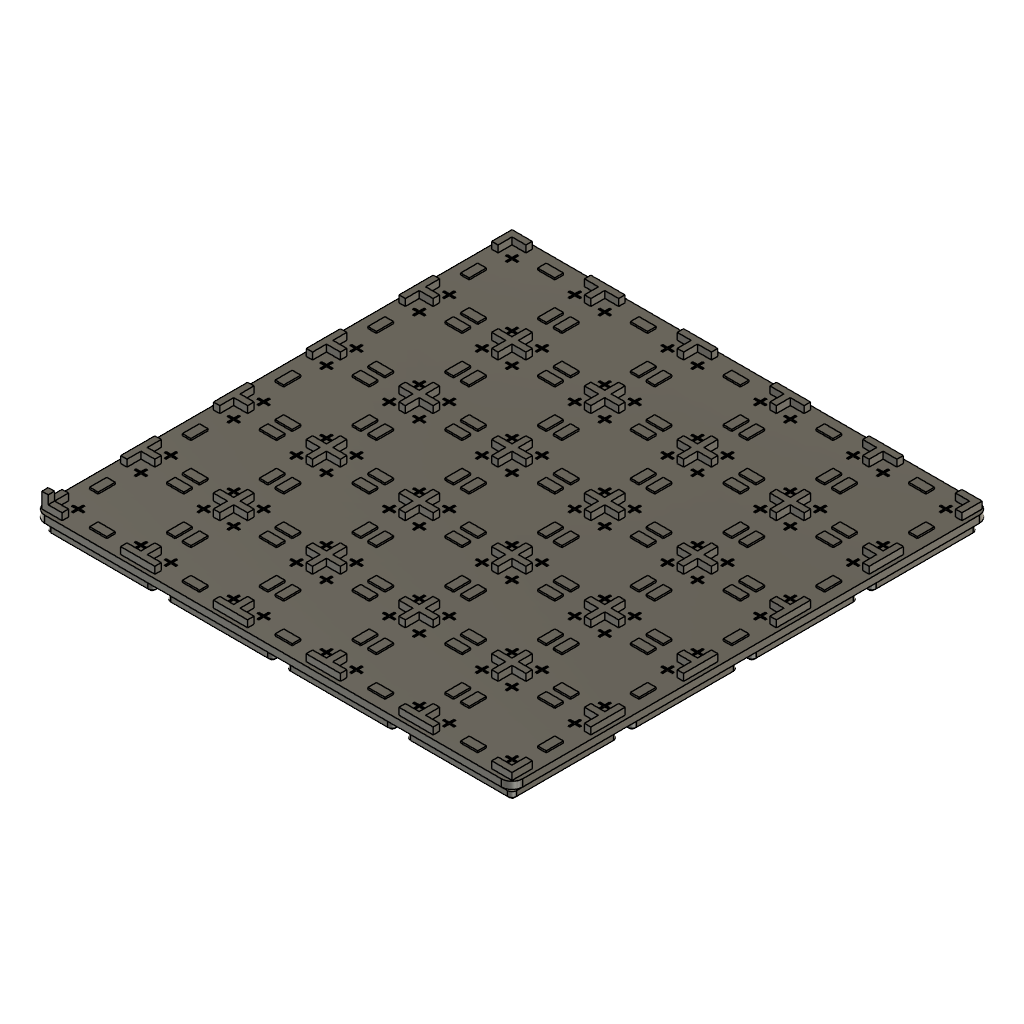
da-lab3-tilgaplaat-v3 (Autodesk Fusion 360 design; units mm, degrees)
part number: 2026-11-14-15-51-29-594
part number: 2026-11-14-15-51-29-835
Autodesk Fusion 360 part; units mm, degrees
(part 1 of 3)
ref_plane "WorkPlane1" through (0, 0, 4.75) normal (0, 0, 1) x (1, 0, 0) in component "drop_plate"
sketch "plate" plane through (0, 0, 4.75) normal (0, 0, 1) x (1, 0, 0) in component "drop_plate"
  line L0 (-80, -83.75) -> (80, -83.75)
  line L1 (83.75, -80) -> (83.75, 80)
  line L2 (80, 83.75) -> (-80, 83.75)
  line L3 (-83.75, 80) -> (-83.75, -80)
  arc A0 (80, -83.75) -> (83.75, -80) centre (80, -80) ccw
  arc A1 (83.75, 80) -> (80, 83.75) centre (80, 80) ccw
  arc A2 (-80, 83.75) -> (-83.75, 80) centre (-80, 80) ccw
  arc A3 (-83.75, -80) -> (-80, -83.75) centre (-80, -80) ccw
  constraint tangent L0 A0
  constraint tangent L1 A0
  constraint tangent L1 A1
  constraint tangent L2 A1
  constraint tangent L2 A2
  constraint tangent L3 A2
  constraint tangent L3 A3
  constraint tangent L0 A3
extrude "plate (1)" add sketch "plate" along normal blind 2.5 in component "drop_plate"
ref_plane "WorkPlane2" through (0, 0, 4.75) normal (0, 0, 1) x (1, 0, 0) in component "drop_plate"
sketch "gf_std_foot1" plane through (0, 0, 4.75) normal (0, 0, 1) x (1, 0, 0) in component "drop_plate"
  line L0 (-46, -42.25) -> (-80, -42.25)
  line L1 (-83.75, -46) -> (-83.75, -80)
  line L2 (-80, -83.75) -> (-46, -83.75)
  line L3 (-42.25, -80) -> (-42.25, -46)
  arc A0 (-80, -42.25) -> (-83.75, -46) centre (-80, -46) ccw
  arc A1 (-83.75, -80) -> (-80, -83.75) centre (-80, -80) ccw
  arc A2 (-46, -83.75) -> (-42.25, -80) centre (-46, -80) ccw
  arc A3 (-42.25, -46) -> (-46, -42.25) centre (-46, -46) ccw
  line L4 (-46, -0.25) -> (-80, -0.25)
  line L5 (-83.75, -4) -> (-83.75, -38)
  line L6 (-80, -41.75) -> (-46, -41.75)
  line L7 (-42.25, -38) -> (-42.25, -4)
  arc A4 (-80, -0.25) -> (-83.75, -4) centre (-80, -4) ccw
  arc A5 (-83.75, -38) -> (-80, -41.75) centre (-80, -38) ccw
  arc A6 (-46, -41.75) -> (-42.25, -38) centre (-46, -38) ccw
  arc A7 (-42.25, -4) -> (-46, -0.25) centre (-46, -4) ccw
  line L8 (-46, 41.75) -> (-80, 41.75)
  line L9 (-83.75, 38) -> (-83.75, 4)
  line L10 (-80, 0.25) -> (-46, 0.25)
  line L11 (-42.25, 4) -> (-42.25, 38)
  arc A8 (-80, 41.75) -> (-83.75, 38) centre (-80, 38) ccw
  arc A9 (-83.75, 4) -> (-80, 0.25) centre (-80, 4) ccw
  arc A10 (-46, 0.25) -> (-42.25, 4) centre (-46, 4) ccw
  arc A11 (-42.25, 38) -> (-46, 41.75) centre (-46, 38) ccw
  line L12 (-46, 83.75) -> (-80, 83.75)
  line L13 (-83.75, 80) -> (-83.75, 46)
  line L14 (-80, 42.25) -> (-46, 42.25)
  line L15 (-42.25, 46) -> (-42.25, 80)
  arc A12 (-80, 83.75) -> (-83.75, 80) centre (-80, 80) ccw
  arc A13 (-83.75, 46) -> (-80, 42.25) centre (-80, 46) ccw
  arc A14 (-46, 42.25) -> (-42.25, 46) centre (-46, 46) ccw
  arc A15 (-42.25, 80) -> (-46, 83.75) centre (-46, 80) ccw
  line L16 (-4, -42.25) -> (-38, -42.25)
  line L17 (-41.75, -46) -> (-41.75, -80)
  line L18 (-38, -83.75) -> (-4, -83.75)
  line L19 (-0.25, -80) -> (-0.25, -46)
  arc A16 (-38, -42.25) -> (-41.75, -46) centre (-38, -46) ccw
  arc A17 (-41.75, -80) -> (-38, -83.75) centre (-38, -80) ccw
  arc A18 (-4, -83.75) -> (-0.25, -80) centre (-4, -80) ccw
  arc A19 (-0.25, -46) -> (-4, -42.25) centre (-4, -46) ccw
  line L20 (-4, -0.25) -> (-38, -0.25)
  line L21 (-41.75, -4) -> (-41.75, -38)
  line L22 (-38, -41.75) -> (-4, -41.75)
  line L23 (-0.25, -38) -> (-0.25, -4)
  arc A20 (-38, -0.25) -> (-41.75, -4) centre (-38, -4) ccw
  arc A21 (-41.75, -38) -> (-38, -41.75) centre (-38, -38) ccw
  arc A22 (-4, -41.75) -> (-0.25, -38) centre (-4, -38) ccw
  arc A23 (-0.25, -4) -> (-4, -0.25) centre (-4, -4) ccw
  line L24 (-4, 41.75) -> (-38, 41.75)
  line L25 (-41.75, 38) -> (-41.75, 4)
  line L26 (-38, 0.25) -> (-4, 0.25)
  line L27 (-0.25, 4) -> (-0.25, 38)
  arc A24 (-38, 41.75) -> (-41.75, 38) centre (-38, 38) ccw
  arc A25 (-41.75, 4) -> (-38, 0.25) centre (-38, 4) ccw
  arc A26 (-4, 0.25) -> (-0.25, 4) centre (-4, 4) ccw
  arc A27 (-0.25, 38) -> (-4, 41.75) centre (-4, 38) ccw
  line L28 (-4, 83.75) -> (-38, 83.75)
  line L29 (-41.75, 80) -> (-41.75, 46)
  line L30 (-38, 42.25) -> (-4, 42.25)
  line L31 (-0.25, 46) -> (-0.25, 80)
  arc A28 (-38, 83.75) -> (-41.75, 80) centre (-38, 80) ccw
  arc A29 (-41.75, 46) -> (-38, 42.25) centre (-38, 46) ccw
  arc A30 (-4, 42.25) -> (-0.25, 46) centre (-4, 46) ccw
  arc A31 (-0.25, 80) -> (-4, 83.75) centre (-4, 80) ccw
  line L32 (38, -42.25) -> (4, -42.25)
  line L33 (0.25, -46) -> (0.25, -80)
  line L34 (4, -83.75) -> (38, -83.75)
  line L35 (41.75, -80) -> (41.75, -46)
  arc A32 (4, -42.25) -> (0.25, -46) centre (4, -46) ccw
  arc A33 (0.25, -80) -> (4, -83.75) centre (4, -80) ccw
  arc A34 (38, -83.75) -> (41.75, -80) centre (38, -80) ccw
  arc A35 (41.75, -46) -> (38, -42.25) centre (38, -46) ccw
  line L36 (38, -0.25) -> (4, -0.25)
  line L37 (0.25, -4) -> (0.25, -38)
  line L38 (4, -41.75) -> (38, -41.75)
  line L39 (41.75, -38) -> (41.75, -4)
  arc A36 (4, -0.25) -> (0.25, -4) centre (4, -4) ccw
  arc A37 (0.25, -38) -> (4, -41.75) centre (4, -38) ccw
  arc A38 (38, -41.75) -> (41.75, -38) centre (38, -38) ccw
  arc A39 (41.75, -4) -> (38, -0.25) centre (38, -4) ccw
  line L40 (38, 41.75) -> (4, 41.75)
  line L41 (0.25, 38) -> (0.25, 4)
  line L42 (4, 0.25) -> (38, 0.25)
  line L43 (41.75, 4) -> (41.75, 38)
  arc A40 (4, 41.75) -> (0.25, 38) centre (4, 38) ccw
  arc A41 (0.25, 4) -> (4, 0.25) centre (4, 4) ccw
  arc A42 (38, 0.25) -> (41.75, 4) centre (38, 4) ccw
  arc A43 (41.75, 38) -> (38, 41.75) centre (38, 38) ccw
  line L44 (38, 83.75) -> (4, 83.75)
  line L45 (0.25, 80) -> (0.25, 46)
  line L46 (4, 42.25) -> (38, 42.25)
  line L47 (41.75, 46) -> (41.75, 80)
  arc A44 (4, 83.75) -> (0.25, 80) centre (4, 80) ccw
  arc A45 (0.25, 46) -> (4, 42.25) centre (4, 46) ccw
  arc A46 (38, 42.25) -> (41.75, 46) centre (38, 46) ccw
  arc A47 (41.75, 80) -> (38, 83.75) centre (38, 80) ccw
  line L48 (80, -42.25) -> (46, -42.25)
  line L49 (42.25, -46) -> (42.25, -80)
  line L50 (46, -83.75) -> (80, -83.75)
  line L51 (83.75, -80) -> (83.75, -46)
  arc A48 (46, -42.25) -> (42.25, -46) centre (46, -46) ccw
  arc A49 (42.25, -80) -> (46, -83.75) centre (46, -80) ccw
  arc A50 (80, -83.75) -> (83.75, -80) centre (80, -80) ccw
  arc A51 (83.75, -46) -> (80, -42.25) centre (80, -46) ccw
  line L52 (80, -0.25) -> (46, -0.25)
  line L53 (42.25, -4) -> (42.25, -38)
  line L54 (46, -41.75) -> (80, -41.75)
  line L55 (83.75, -38) -> (83.75, -4)
  arc A52 (46, -0.25) -> (42.25, -4) centre (46, -4) ccw
  arc A53 (42.25, -38) -> (46, -41.75) centre (46, -38) ccw
  arc A54 (80, -41.75) -> (83.75, -38) centre (80, -38) ccw
  arc A55 (83.75, -4) -> (80, -0.25) centre (80, -4) ccw
  line L56 (80, 41.75) -> (46, 41.75)
  line L57 (42.25, 38) -> (42.25, 4)
  line L58 (46, 0.25) -> (80, 0.25)
  line L59 (83.75, 4) -> (83.75, 38)
  arc A56 (46, 41.75) -> (42.25, 38) centre (46, 38) ccw
  arc A57 (42.25, 4) -> (46, 0.25) centre (46, 4) ccw
  arc A58 (80, 0.25) -> (83.75, 4) centre (80, 4) ccw
  arc A59 (83.75, 38) -> (80, 41.75) centre (80, 38) ccw
  line L60 (80, 83.75) -> (46, 83.75)
  line L61 (42.25, 80) -> (42.25, 46)
  line L62 (46, 42.25) -> (80, 42.25)
  line L63 (83.75, 46) -> (83.75, 80)
  arc A60 (46, 83.75) -> (42.25, 80) centre (46, 80) ccw
  arc A61 (42.25, 46) -> (46, 42.25) centre (46, 46) ccw
  arc A62 (80, 42.25) -> (83.75, 46) centre (80, 46) ccw
  arc A63 (83.75, 80) -> (80, 83.75) centre (80, 80) ccw
  constraint tangent L0 A0
  constraint tangent L1 A0
  constraint tangent L1 A1
  constraint tangent L2 A1
  constraint tangent L2 A2
  constraint tangent L3 A2
  constraint tangent L3 A3
  constraint tangent L0 A3
  constraint tangent L4 A4
  constraint tangent L5 A4
  constraint tangent L5 A5
  constraint tangent L6 A5
  constraint tangent L6 A6
  constraint tangent L7 A6
  constraint tangent L7 A7
  constraint tangent L4 A7
  constraint tangent L8 A8
  constraint tangent L9 A8
  constraint tangent L9 A9
  constraint tangent L10 A9
  constraint tangent L10 A10
  constraint tangent L11 A10
  constraint tangent L11 A11
  constraint tangent L8 A11
  constraint tangent L12 A12
  constraint tangent L13 A12
  constraint tangent L13 A13
  constraint tangent L14 A13
  constraint tangent L14 A14
  constraint tangent L15 A14
  constraint tangent L15 A15
  constraint tangent L12 A15
  constraint tangent L16 A16
  constraint tangent L17 A16
  constraint tangent L17 A17
  constraint tangent L18 A17
  constraint tangent L18 A18
  constraint tangent L19 A18
  constraint tangent L19 A19
  constraint tangent L16 A19
  constraint tangent L20 A20
  constraint tangent L21 A20
  constraint tangent L21 A21
  constraint tangent L22 A21
  constraint tangent L22 A22
  constraint tangent L23 A22
  constraint tangent L23 A23
  constraint tangent L20 A23
  constraint tangent L24 A24
  constraint tangent L25 A24
  constraint tangent L25 A25
  constraint tangent L26 A25
  constraint tangent L26 A26
  constraint tangent L27 A26
  constraint tangent L27 A27
  constraint tangent L24 A27
  constraint tangent L28 A28
  constraint tangent L29 A28
  constraint tangent L29 A29
  constraint tangent L30 A29
  constraint tangent L30 A30
  constraint tangent L31 A30
  constraint tangent L31 A31
  constraint tangent L28 A31
  constraint tangent L32 A32
  constraint tangent L33 A32
  constraint tangent L33 A33
  constraint tangent L34 A33
  constraint tangent L34 A34
  constraint tangent L35 A34
  constraint tangent L35 A35
  constraint tangent L32 A35
  constraint tangent L36 A36
  constraint tangent L37 A36
  constraint tangent L37 A37
  constraint tangent L38 A37
  constraint tangent L38 A38
  constraint tangent L39 A38
  constraint tangent L39 A39
  constraint tangent L36 A39
  constraint tangent L40 A40
  constraint tangent L41 A40
  constraint tangent L41 A41
  constraint tangent L42 A41
  constraint tangent L42 A42
  constraint tangent L43 A42
  constraint tangent L43 A43
  constraint tangent L40 A43
  constraint tangent L44 A44
  constraint tangent L45 A44
  constraint tangent L45 A45
  constraint tangent L46 A45
  constraint tangent L46 A46
  constraint tangent L47 A46
  constraint tangent L47 A47
  constraint tangent L44 A47
  constraint tangent L48 A48
  constraint tangent L49 A48
  constraint tangent L49 A49
  constraint tangent L50 A49
  constraint tangent L50 A50
  constraint tangent L51 A50
  constraint tangent L51 A51
  constraint tangent L48 A51
  constraint tangent L52 A52
  constraint tangent L53 A52
  constraint tangent L53 A53
  constraint tangent L54 A53
  constraint tangent L54 A54
  constraint tangent L55 A54
  constraint tangent L55 A55
  constraint tangent L52 A55
  constraint tangent L56 A56
  constraint tangent L57 A56
  constraint tangent L57 A57
  constraint tangent L58 A57
  constraint tangent L58 A58
  constraint tangent L59 A58
  constraint tangent L59 A59
  constraint tangent L56 A59
  constraint tangent L60 A60
  constraint tangent L61 A60
  constraint tangent L61 A61
  constraint tangent L62 A61
  constraint tangent L62 A62
  constraint tangent L63 A62
  constraint tangent L63 A63
  constraint tangent L60 A63
extrude "gf_std_foot1 (1)" add sketch "gf_std_foot1" against normal blind 2.15 draft -45 in component "drop_plate"
ref_plane "WorkPlane3" through (0, 0, 2.6) normal (0, 0, 1) x (1, 0, 0) in component "drop_plate"
sketch "gf_std_foot2" plane through (0, 0, 2.6) normal (0, 0, 1) x (1, 0, 0) in component "drop_plate"
  line L0 (-46, -44.4) -> (-80, -44.4)
  line L1 (-81.6, -46) -> (-81.6, -80)
  line L2 (-80, -81.6) -> (-46, -81.6)
  line L3 (-44.4, -80) -> (-44.4, -46)
  arc A0 (-80, -44.4) -> (-81.6, -46) centre (-80, -46) ccw
  arc A1 (-81.6, -80) -> (-80, -81.6) centre (-80, -80) ccw
  arc A2 (-46, -81.6) -> (-44.4, -80) centre (-46, -80) ccw
  arc A3 (-44.4, -46) -> (-46, -44.4) centre (-46, -46) ccw
  line L4 (-46, -2.4) -> (-80, -2.4)
  line L5 (-81.6, -4) -> (-81.6, -38)
  line L6 (-80, -39.6) -> (-46, -39.6)
  line L7 (-44.4, -38) -> (-44.4, -4)
  arc A4 (-80, -2.4) -> (-81.6, -4) centre (-80, -4) ccw
  arc A5 (-81.6, -38) -> (-80, -39.6) centre (-80, -38) ccw
  arc A6 (-46, -39.6) -> (-44.4, -38) centre (-46, -38) ccw
  arc A7 (-44.4, -4) -> (-46, -2.4) centre (-46, -4) ccw
  line L8 (-46, 39.6) -> (-80, 39.6)
  line L9 (-81.6, 38) -> (-81.6, 4)
  line L10 (-80, 2.4) -> (-46, 2.4)
  line L11 (-44.4, 4) -> (-44.4, 38)
  arc A8 (-80, 39.6) -> (-81.6, 38) centre (-80, 38) ccw
  arc A9 (-81.6, 4) -> (-80, 2.4) centre (-80, 4) ccw
  arc A10 (-46, 2.4) -> (-44.4, 4) centre (-46, 4) ccw
  arc A11 (-44.4, 38) -> (-46, 39.6) centre (-46, 38) ccw
  line L12 (-46, 81.6) -> (-80, 81.6)
  line L13 (-81.6, 80) -> (-81.6, 46)
  line L14 (-80, 44.4) -> (-46, 44.4)
  line L15 (-44.4, 46) -> (-44.4, 80)
  arc A12 (-80, 81.6) -> (-81.6, 80) centre (-80, 80) ccw
  arc A13 (-81.6, 46) -> (-80, 44.4) centre (-80, 46) ccw
  arc A14 (-46, 44.4) -> (-44.4, 46) centre (-46, 46) ccw
  arc A15 (-44.4, 80) -> (-46, 81.6) centre (-46, 80) ccw
  line L16 (-4, -44.4) -> (-38, -44.4)
  line L17 (-39.6, -46) -> (-39.6, -80)
  line L18 (-38, -81.6) -> (-4, -81.6)
  line L19 (-2.4, -80) -> (-2.4, -46)
  arc A16 (-38, -44.4) -> (-39.6, -46) centre (-38, -46) ccw
  arc A17 (-39.6, -80) -> (-38, -81.6) centre (-38, -80) ccw
  arc A18 (-4, -81.6) -> (-2.4, -80) centre (-4, -80) ccw
  arc A19 (-2.4, -46) -> (-4, -44.4) centre (-4, -46) ccw
  line L20 (-4, -2.4) -> (-38, -2.4)
  line L21 (-39.6, -4) -> (-39.6, -38)
  line L22 (-38, -39.6) -> (-4, -39.6)
  line L23 (-2.4, -38) -> (-2.4, -4)
  arc A20 (-38, -2.4) -> (-39.6, -4) centre (-38, -4) ccw
  arc A21 (-39.6, -38) -> (-38, -39.6) centre (-38, -38) ccw
  arc A22 (-4, -39.6) -> (-2.4, -38) centre (-4, -38) ccw
  arc A23 (-2.4, -4) -> (-4, -2.4) centre (-4, -4) ccw
  line L24 (-4, 39.6) -> (-38, 39.6)
  line L25 (-39.6, 38) -> (-39.6, 4)
  line L26 (-38, 2.4) -> (-4, 2.4)
  line L27 (-2.4, 4) -> (-2.4, 38)
  arc A24 (-38, 39.6) -> (-39.6, 38) centre (-38, 38) ccw
  arc A25 (-39.6, 4) -> (-38, 2.4) centre (-38, 4) ccw
  arc A26 (-4, 2.4) -> (-2.4, 4) centre (-4, 4) ccw
  arc A27 (-2.4, 38) -> (-4, 39.6) centre (-4, 38) ccw
  line L28 (-4, 81.6) -> (-38, 81.6)
  line L29 (-39.6, 80) -> (-39.6, 46)
  line L30 (-38, 44.4) -> (-4, 44.4)
  line L31 (-2.4, 46) -> (-2.4, 80)
  arc A28 (-38, 81.6) -> (-39.6, 80) centre (-38, 80) ccw
  arc A29 (-39.6, 46) -> (-38, 44.4) centre (-38, 46) ccw
  arc A30 (-4, 44.4) -> (-2.4, 46) centre (-4, 46) ccw
  arc A31 (-2.4, 80) -> (-4, 81.6) centre (-4, 80) ccw
  line L32 (38, -44.4) -> (4, -44.4)
  line L33 (2.4, -46) -> (2.4, -80)
  line L34 (4, -81.6) -> (38, -81.6)
  line L35 (39.6, -80) -> (39.6, -46)
  arc A32 (4, -44.4) -> (2.4, -46) centre (4, -46) ccw
  arc A33 (2.4, -80) -> (4, -81.6) centre (4, -80) ccw
  arc A34 (38, -81.6) -> (39.6, -80) centre (38, -80) ccw
  arc A35 (39.6, -46) -> (38, -44.4) centre (38, -46) ccw
  line L36 (38, -2.4) -> (4, -2.4)
  line L37 (2.4, -4) -> (2.4, -38)
  line L38 (4, -39.6) -> (38, -39.6)
  line L39 (39.6, -38) -> (39.6, -4)
  arc A36 (4, -2.4) -> (2.4, -4) centre (4, -4) ccw
  arc A37 (2.4, -38) -> (4, -39.6) centre (4, -38) ccw
  arc A38 (38, -39.6) -> (39.6, -38) centre (38, -38) ccw
  arc A39 (39.6, -4) -> (38, -2.4) centre (38, -4) ccw
  line L40 (38, 39.6) -> (4, 39.6)
  line L41 (2.4, 38) -> (2.4, 4)
  line L42 (4, 2.4) -> (38, 2.4)
  line L43 (39.6, 4) -> (39.6, 38)
  arc A40 (4, 39.6) -> (2.4, 38) centre (4, 38) ccw
  arc A41 (2.4, 4) -> (4, 2.4) centre (4, 4) ccw
  arc A42 (38, 2.4) -> (39.6, 4) centre (38, 4) ccw
  arc A43 (39.6, 38) -> (38, 39.6) centre (38, 38) ccw
  line L44 (38, 81.6) -> (4, 81.6)
  line L45 (2.4, 80) -> (2.4, 46)
  line L46 (4, 44.4) -> (38, 44.4)
  line L47 (39.6, 46) -> (39.6, 80)
  arc A44 (4, 81.6) -> (2.4, 80) centre (4, 80) ccw
  arc A45 (2.4, 46) -> (4, 44.4) centre (4, 46) ccw
  arc A46 (38, 44.4) -> (39.6, 46) centre (38, 46) ccw
  arc A47 (39.6, 80) -> (38, 81.6) centre (38, 80) ccw
  line L48 (80, -44.4) -> (46, -44.4)
  line L49 (44.4, -46) -> (44.4, -80)
  line L50 (46, -81.6) -> (80, -81.6)
  line L51 (81.6, -80) -> (81.6, -46)
  arc A48 (46, -44.4) -> (44.4, -46) centre (46, -46) ccw
  arc A49 (44.4, -80) -> (46, -81.6) centre (46, -80) ccw
  arc A50 (80, -81.6) -> (81.6, -80) centre (80, -80) ccw
  arc A51 (81.6, -46) -> (80, -44.4) centre (80, -46) ccw
  line L52 (80, -2.4) -> (46, -2.4)
  line L53 (44.4, -4) -> (44.4, -38)
  line L54 (46, -39.6) -> (80, -39.6)
  line L55 (81.6, -38) -> (81.6, -4)
  arc A52 (46, -2.4) -> (44.4, -4) centre (46, -4) ccw
  arc A53 (44.4, -38) -> (46, -39.6) centre (46, -38) ccw
  arc A54 (80, -39.6) -> (81.6, -38) centre (80, -38) ccw
  arc A55 (81.6, -4) -> (80, -2.4) centre (80, -4) ccw
  line L56 (80, 39.6) -> (46, 39.6)
  line L57 (44.4, 38) -> (44.4, 4)
  line L58 (46, 2.4) -> (80, 2.4)
  line L59 (81.6, 4) -> (81.6, 38)
  arc A56 (46, 39.6) -> (44.4, 38) centre (46, 38) ccw
  arc A57 (44.4, 4) -> (46, 2.4) centre (46, 4) ccw
  arc A58 (80, 2.4) -> (81.6, 4) centre (80, 4) ccw
  arc A59 (81.6, 38) -> (80, 39.6) centre (80, 38) ccw
  line L60 (80, 81.6) -> (46, 81.6)
  line L61 (44.4, 80) -> (44.4, 46)
  line L62 (46, 44.4) -> (80, 44.4)
  line L63 (81.6, 46) -> (81.6, 80)
  arc A60 (46, 81.6) -> (44.4, 80) centre (46, 80) ccw
  arc A61 (44.4, 46) -> (46, 44.4) centre (46, 46) ccw
  arc A62 (80, 44.4) -> (81.6, 46) centre (80, 46) ccw
  arc A63 (81.6, 80) -> (80, 81.6) centre (80, 80) ccw
  constraint tangent L0 A0
  constraint tangent L1 A0
  constraint tangent L1 A1
  constraint tangent L2 A1
  constraint tangent L2 A2
  constraint tangent L3 A2
  constraint tangent L3 A3
  constraint tangent L0 A3
  constraint tangent L4 A4
  constraint tangent L5 A4
  constraint tangent L5 A5
  constraint tangent L6 A5
  constraint tangent L6 A6
  constraint tangent L7 A6
  constraint tangent L7 A7
  constraint tangent L4 A7
  constraint tangent L8 A8
  constraint tangent L9 A8
  constraint tangent L9 A9
  constraint tangent L10 A9
  constraint tangent L10 A10
  constraint tangent L11 A10
  constraint tangent L11 A11
  constraint tangent L8 A11
  constraint tangent L12 A12
  constraint tangent L13 A12
  constraint tangent L13 A13
  constraint tangent L14 A13
  constraint tangent L14 A14
  constraint tangent L15 A14
  constraint tangent L15 A15
  constraint tangent L12 A15
  constraint tangent L16 A16
  constraint tangent L17 A16
  constraint tangent L17 A17
  constraint tangent L18 A17
  constraint tangent L18 A18
  constraint tangent L19 A18
  constraint tangent L19 A19
  constraint tangent L16 A19
  constraint tangent L20 A20
  constraint tangent L21 A20
  constraint tangent L21 A21
  constraint tangent L22 A21
  constraint tangent L22 A22
  constraint tangent L23 A22
  constraint tangent L23 A23
  constraint tangent L20 A23
  constraint tangent L24 A24
  constraint tangent L25 A24
  constraint tangent L25 A25
  constraint tangent L26 A25
  constraint tangent L26 A26
  constraint tangent L27 A26
  constraint tangent L27 A27
  constraint tangent L24 A27
  constraint tangent L28 A28
  constraint tangent L29 A28
  constraint tangent L29 A29
  constraint tangent L30 A29
  constraint tangent L30 A30
  constraint tangent L31 A30
  constraint tangent L31 A31
  constraint tangent L28 A31
  constraint tangent L32 A32
  constraint tangent L33 A32
  constraint tangent L33 A33
  constraint tangent L34 A33
  constraint tangent L34 A34
  constraint tangent L35 A34
  constraint tangent L35 A35
  constraint tangent L32 A35
  constraint tangent L36 A36
  constraint tangent L37 A36
  constraint tangent L37 A37
  constraint tangent L38 A37
  constraint tangent L38 A38
  constraint tangent L39 A38
  constraint tangent L39 A39
  constraint tangent L36 A39
  constraint tangent L40 A40
  constraint tangent L41 A40
  constraint tangent L41 A41
  constraint tangent L42 A41
  constraint tangent L42 A42
  constraint tangent L43 A42
  constraint tangent L43 A43
  constraint tangent L40 A43
  constraint tangent L44 A44
  constraint tangent L45 A44
  constraint tangent L45 A45
  constraint tangent L46 A45
  constraint tangent L46 A46
  constraint tangent L47 A46
  constraint tangent L47 A47
  constraint tangent L44 A47
  constraint tangent L48 A48
  constraint tangent L49 A48
  constraint tangent L49 A49
  constraint tangent L50 A49
  constraint tangent L50 A50
  constraint tangent L51 A50
  constraint tangent L51 A51
  constraint tangent L48 A51
  constraint tangent L52 A52
  constraint tangent L53 A52
  constraint tangent L53 A53
  constraint tangent L54 A53
  constraint tangent L54 A54
  constraint tangent L55 A54
  constraint tangent L55 A55
  constraint tangent L52 A55
  constraint tangent L56 A56
  constraint tangent L57 A56
  constraint tangent L57 A57
  constraint tangent L58 A57
  constraint tangent L58 A58
  constraint tangent L59 A58
  constraint tangent L59 A59
  constraint tangent L56 A59
  constraint tangent L60 A60
  constraint tangent L61 A60
  constraint tangent L61 A61
  constraint tangent L62 A61
  constraint tangent L62 A62
  constraint tangent L63 A62
  constraint tangent L63 A63
  constraint tangent L60 A63
extrude "gf_std_foot2 (1)" add sketch "gf_std_foot2" against normal blind 1.8 in component "drop_plate"
ref_plane "WorkPlane4" through (0, 0, 0.8) normal (0, 0, 1) x (1, 0, 0) in component "drop_plate"
sketch "gf_std_foot3" plane through (0, 0, 0.8) normal (0, 0, 1) x (1, 0, 0) in component "drop_plate"
  line L0 (-46, -44.4) -> (-80, -44.4)
  line L1 (-81.6, -46) -> (-81.6, -80)
  line L2 (-80, -81.6) -> (-46, -81.6)
  line L3 (-44.4, -80) -> (-44.4, -46)
  arc A0 (-80, -44.4) -> (-81.6, -46) centre (-80, -46) ccw
  arc A1 (-81.6, -80) -> (-80, -81.6) centre (-80, -80) ccw
  arc A2 (-46, -81.6) -> (-44.4, -80) centre (-46, -80) ccw
  arc A3 (-44.4, -46) -> (-46, -44.4) centre (-46, -46) ccw
  line L4 (-46, -2.4) -> (-80, -2.4)
  line L5 (-81.6, -4) -> (-81.6, -38)
  line L6 (-80, -39.6) -> (-46, -39.6)
  line L7 (-44.4, -38) -> (-44.4, -4)
  arc A4 (-80, -2.4) -> (-81.6, -4) centre (-80, -4) ccw
  arc A5 (-81.6, -38) -> (-80, -39.6) centre (-80, -38) ccw
  arc A6 (-46, -39.6) -> (-44.4, -38) centre (-46, -38) ccw
  arc A7 (-44.4, -4) -> (-46, -2.4) centre (-46, -4) ccw
  line L8 (-46, 39.6) -> (-80, 39.6)
  line L9 (-81.6, 38) -> (-81.6, 4)
  line L10 (-80, 2.4) -> (-46, 2.4)
  line L11 (-44.4, 4) -> (-44.4, 38)
  arc A8 (-80, 39.6) -> (-81.6, 38) centre (-80, 38) ccw
  arc A9 (-81.6, 4) -> (-80, 2.4) centre (-80, 4) ccw
  arc A10 (-46, 2.4) -> (-44.4, 4) centre (-46, 4) ccw
  arc A11 (-44.4, 38) -> (-46, 39.6) centre (-46, 38) ccw
  line L12 (-46, 81.6) -> (-80, 81.6)
  line L13 (-81.6, 80) -> (-81.6, 46)
  line L14 (-80, 44.4) -> (-46, 44.4)
  line L15 (-44.4, 46) -> (-44.4, 80)
  arc A12 (-80, 81.6) -> (-81.6, 80) centre (-80, 80) ccw
  arc A13 (-81.6, 46) -> (-80, 44.4) centre (-80, 46) ccw
  arc A14 (-46, 44.4) -> (-44.4, 46) centre (-46, 46) ccw
  arc A15 (-44.4, 80) -> (-46, 81.6) centre (-46, 80) ccw
  line L16 (-4, -44.4) -> (-38, -44.4)
  line L17 (-39.6, -46) -> (-39.6, -80)
  line L18 (-38, -81.6) -> (-4, -81.6)
  line L19 (-2.4, -80) -> (-2.4, -46)
  arc A16 (-38, -44.4) -> (-39.6, -46) centre (-38, -46) ccw
  arc A17 (-39.6, -80) -> (-38, -81.6) centre (-38, -80) ccw
  arc A18 (-4, -81.6) -> (-2.4, -80) centre (-4, -80) ccw
  arc A19 (-2.4, -46) -> (-4, -44.4) centre (-4, -46) ccw
  line L20 (-4, -2.4) -> (-38, -2.4)
  line L21 (-39.6, -4) -> (-39.6, -38)
  line L22 (-38, -39.6) -> (-4, -39.6)
  line L23 (-2.4, -38) -> (-2.4, -4)
  arc A20 (-38, -2.4) -> (-39.6, -4) centre (-38, -4) ccw
  arc A21 (-39.6, -38) -> (-38, -39.6) centre (-38, -38) ccw
  arc A22 (-4, -39.6) -> (-2.4, -38) centre (-4, -38) ccw
  arc A23 (-2.4, -4) -> (-4, -2.4) centre (-4, -4) ccw
  line L24 (-4, 39.6) -> (-38, 39.6)
  line L25 (-39.6, 38) -> (-39.6, 4)
  line L26 (-38, 2.4) -> (-4, 2.4)
  line L27 (-2.4, 4) -> (-2.4, 38)
  arc A24 (-38, 39.6) -> (-39.6, 38) centre (-38, 38) ccw
  arc A25 (-39.6, 4) -> (-38, 2.4) centre (-38, 4) ccw
  arc A26 (-4, 2.4) -> (-2.4, 4) centre (-4, 4) ccw
  arc A27 (-2.4, 38) -> (-4, 39.6) centre (-4, 38) ccw
  line L28 (-4, 81.6) -> (-38, 81.6)
  line L29 (-39.6, 80) -> (-39.6, 46)
  line L30 (-38, 44.4) -> (-4, 44.4)
  line L31 (-2.4, 46) -> (-2.4, 80)
  arc A28 (-38, 81.6) -> (-39.6, 80) centre (-38, 80) ccw
  arc A29 (-39.6, 46) -> (-38, 44.4) centre (-38, 46) ccw
  arc A30 (-4, 44.4) -> (-2.4, 46) centre (-4, 46) ccw
  arc A31 (-2.4, 80) -> (-4, 81.6) centre (-4, 80) ccw
  line L32 (38, -44.4) -> (4, -44.4)
  line L33 (2.4, -46) -> (2.4, -80)
  line L34 (4, -81.6) -> (38, -81.6)
  line L35 (39.6, -80) -> (39.6, -46)
  arc A32 (4, -44.4) -> (2.4, -46) centre (4, -46) ccw
  arc A33 (2.4, -80) -> (4, -81.6) centre (4, -80) ccw
  arc A34 (38, -81.6) -> (39.6, -80) centre (38, -80) ccw
  arc A35 (39.6, -46) -> (38, -44.4) centre (38, -46) ccw
  line L36 (38, -2.4) -> (4, -2.4)
  line L37 (2.4, -4) -> (2.4, -38)
  line L38 (4, -39.6) -> (38, -39.6)
  line L39 (39.6, -38) -> (39.6, -4)
  arc A36 (4, -2.4) -> (2.4, -4) centre (4, -4) ccw
  arc A37 (2.4, -38) -> (4, -39.6) centre (4, -38) ccw
  arc A38 (38, -39.6) -> (39.6, -38) centre (38, -38) ccw
  arc A39 (39.6, -4) -> (38, -2.4) centre (38, -4) ccw
  line L40 (38, 39.6) -> (4, 39.6)
  line L41 (2.4, 38) -> (2.4, 4)
  line L42 (4, 2.4) -> (38, 2.4)
  line L43 (39.6, 4) -> (39.6, 38)
  arc A40 (4, 39.6) -> (2.4, 38) centre (4, 38) ccw
  arc A41 (2.4, 4) -> (4, 2.4) centre (4, 4) ccw
  arc A42 (38, 2.4) -> (39.6, 4) centre (38, 4) ccw
  arc A43 (39.6, 38) -> (38, 39.6) centre (38, 38) ccw
  line L44 (38, 81.6) -> (4, 81.6)
  line L45 (2.4, 80) -> (2.4, 46)
  line L46 (4, 44.4) -> (38, 44.4)
  line L47 (39.6, 46) -> (39.6, 80)
  arc A44 (4, 81.6) -> (2.4, 80) centre (4, 80) ccw
  arc A45 (2.4, 46) -> (4, 44.4) centre (4, 46) ccw
  arc A46 (38, 44.4) -> (39.6, 46) centre (38, 46) ccw
  arc A47 (39.6, 80) -> (38, 81.6) centre (38, 80) ccw
  line L48 (80, -44.4) -> (46, -44.4)
  line L49 (44.4, -46) -> (44.4, -80)
  line L50 (46, -81.6) -> (80, -81.6)
  line L51 (81.6, -80) -> (81.6, -46)
  arc A48 (46, -44.4) -> (44.4, -46) centre (46, -46) ccw
  arc A49 (44.4, -80) -> (46, -81.6) centre (46, -80) ccw
  arc A50 (80, -81.6) -> (81.6, -80) centre (80, -80) ccw
  arc A51 (81.6, -46) -> (80, -44.4) centre (80, -46) ccw
  line L52 (80, -2.4) -> (46, -2.4)
  line L53 (44.4, -4) -> (44.4, -38)
  line L54 (46, -39.6) -> (80, -39.6)
  line L55 (81.6, -38) -> (81.6, -4)
  arc A52 (46, -2.4) -> (44.4, -4) centre (46, -4) ccw
  arc A53 (44.4, -38) -> (46, -39.6) centre (46, -38) ccw
  arc A54 (80, -39.6) -> (81.6, -38) centre (80, -38) ccw
  arc A55 (81.6, -4) -> (80, -2.4) centre (80, -4) ccw
  line L56 (80, 39.6) -> (46, 39.6)
  line L57 (44.4, 38) -> (44.4, 4)
  line L58 (46, 2.4) -> (80, 2.4)
  line L59 (81.6, 4) -> (81.6, 38)
  arc A56 (46, 39.6) -> (44.4, 38) centre (46, 38) ccw
  arc A57 (44.4, 4) -> (46, 2.4) centre (46, 4) ccw
  arc A58 (80, 2.4) -> (81.6, 4) centre (80, 4) ccw
  arc A59 (81.6, 38) -> (80, 39.6) centre (80, 38) ccw
  line L60 (80, 81.6) -> (46, 81.6)
  line L61 (44.4, 80) -> (44.4, 46)
  line L62 (46, 44.4) -> (80, 44.4)
  line L63 (81.6, 46) -> (81.6, 80)
  arc A60 (46, 81.6) -> (44.4, 80) centre (46, 80) ccw
  arc A61 (44.4, 46) -> (46, 44.4) centre (46, 46) ccw
  arc A62 (80, 44.4) -> (81.6, 46) centre (80, 46) ccw
  arc A63 (81.6, 80) -> (80, 81.6) centre (80, 80) ccw
  constraint tangent L0 A0
  constraint tangent L1 A0
  constraint tangent L1 A1
  constraint tangent L2 A1
  constraint tangent L2 A2
  constraint tangent L3 A2
  constraint tangent L3 A3
  constraint tangent L0 A3
  constraint tangent L4 A4
  constraint tangent L5 A4
  constraint tangent L5 A5
  constraint tangent L6 A5
  constraint tangent L6 A6
  constraint tangent L7 A6
  constraint tangent L7 A7
  constraint tangent L4 A7
  constraint tangent L8 A8
  constraint tangent L9 A8
  constraint tangent L9 A9
  constraint tangent L10 A9
  constraint tangent L10 A10
  constraint tangent L11 A10
  constraint tangent L11 A11
  constraint tangent L8 A11
  constraint tangent L12 A12
  constraint tangent L13 A12
  constraint tangent L13 A13
  constraint tangent L14 A13
  constraint tangent L14 A14
  constraint tangent L15 A14
  constraint tangent L15 A15
  constraint tangent L12 A15
  constraint tangent L16 A16
  constraint tangent L17 A16
  constraint tangent L17 A17
  constraint tangent L18 A17
  constraint tangent L18 A18
  constraint tangent L19 A18
  constraint tangent L19 A19
  constraint tangent L16 A19
  constraint tangent L20 A20
  constraint tangent L21 A20
  constraint tangent L21 A21
  constraint tangent L22 A21
  constraint tangent L22 A22
  constraint tangent L23 A22
  constraint tangent L23 A23
  constraint tangent L20 A23
  constraint tangent L24 A24
  constraint tangent L25 A24
  constraint tangent L25 A25
  constraint tangent L26 A25
  constraint tangent L26 A26
  constraint tangent L27 A26
  constraint tangent L27 A27
  constraint tangent L24 A27
  constraint tangent L28 A28
  constraint tangent L29 A28
  constraint tangent L29 A29
  constraint tangent L30 A29
  constraint tangent L30 A30
  constraint tangent L31 A30
  constraint tangent L31 A31
  constraint tangent L28 A31
  constraint tangent L32 A32
  constraint tangent L33 A32
  constraint tangent L33 A33
  constraint tangent L34 A33
  constraint tangent L34 A34
  constraint tangent L35 A34
  constraint tangent L35 A35
  constraint tangent L32 A35
  constraint tangent L36 A36
  constraint tangent L37 A36
  constraint tangent L37 A37
  constraint tangent L38 A37
  constraint tangent L38 A38
  constraint tangent L39 A38
  constraint tangent L39 A39
  constraint tangent L36 A39
  constraint tangent L40 A40
  constraint tangent L41 A40
  constraint tangent L41 A41
  constraint tangent L42 A41
  constraint tangent L42 A42
  constraint tangent L43 A42
  constraint tangent L43 A43
  constraint tangent L40 A43
  constraint tangent L44 A44
  constraint tangent L45 A44
  constraint tangent L45 A45
  constraint tangent L46 A45
  constraint tangent L46 A46
  constraint tangent L47 A46
  constraint tangent L47 A47
  constraint tangent L44 A47
  constraint tangent L48 A48
  constraint tangent L49 A48
  constraint tangent L49 A49
  constraint tangent L50 A49
  constraint tangent L50 A50
  constraint tangent L51 A50
  constraint tangent L51 A51
  constraint tangent L48 A51
  constraint tangent L52 A52
  constraint tangent L53 A52
  constraint tangent L53 A53
  constraint tangent L54 A53
  constraint tangent L54 A54
  constraint tangent L55 A54
  constraint tangent L55 A55
  constraint tangent L52 A55
  constraint tangent L56 A56
  constraint tangent L57 A56
  constraint tangent L57 A57
  constraint tangent L58 A57
  constraint tangent L58 A58
  constraint tangent L59 A58
  constraint tangent L59 A59
  constraint tangent L56 A59
  constraint tangent L60 A60
  constraint tangent L61 A60
  constraint tangent L61 A61
  constraint tangent L62 A61
  constraint tangent L62 A62
  constraint tangent L63 A62
  constraint tangent L63 A63
  constraint tangent L60 A63
extrude "gf_std_foot3 (1)" add sketch "gf_std_foot3" against normal blind 0.8 draft -45 in component "drop_plate"
ref_plane "WorkPlane5" through (0, 0, 7.25) normal (0, 0, 1) x (1, 0, 0) in component "drop_plate"
sketch "spacer_pads" plane through (0, 0, 7.25) normal (0, 0, 1) x (1, 0, 0) in component "drop_plate"
  line L0 (-80, -68) -> (-77, -68)
  line L1 (-77, -68) -> (-77, -62)
  line L2 (-77, -62) -> (-80, -62)
  line L3 (-80, -62) -> (-80, -68)
  line L4 (-53, -68) -> (-50, -68)
  line L5 (-50, -68) -> (-50, -62)
  line L6 (-50, -62) -> (-53, -62)
  line L7 (-53, -62) -> (-53, -68)
  line L8 (-68, -80) -> (-62, -80)
  line L9 (-62, -80) -> (-62, -77)
  line L10 (-62, -77) -> (-68, -77)
  line L11 (-68, -77) -> (-68, -80)
  line L12 (-68, -53) -> (-62, -53)
  line L13 (-62, -53) -> (-62, -50)
  line L14 (-62, -50) -> (-68, -50)
  line L15 (-68, -50) -> (-68, -53)
  line L16 (-80, -35.5) -> (-77, -35.5)
  line L17 (-77, -35.5) -> (-77, -29.5)
  line L18 (-77, -29.5) -> (-80, -29.5)
  line L19 (-80, -29.5) -> (-80, -35.5)
  line L20 (-53, -35.5) -> (-50, -35.5)
  line L21 (-50, -35.5) -> (-50, -29.5)
  line L22 (-50, -29.5) -> (-53, -29.5)
  line L23 (-53, -29.5) -> (-53, -35.5)
  line L24 (-68, -47.5) -> (-62, -47.5)
  line L25 (-62, -47.5) -> (-62, -44.5)
  line L26 (-62, -44.5) -> (-68, -44.5)
  line L27 (-68, -44.5) -> (-68, -47.5)
  line L28 (-68, -20.5) -> (-62, -20.5)
  line L29 (-62, -20.5) -> (-62, -17.5)
  line L30 (-62, -17.5) -> (-68, -17.5)
  line L31 (-68, -17.5) -> (-68, -20.5)
  line L32 (-80, -3) -> (-77, -3)
  line L33 (-77, -3) -> (-77, 3)
  line L34 (-77, 3) -> (-80, 3)
  line L35 (-80, 3) -> (-80, -3)
  line L36 (-53, -3) -> (-50, -3)
  line L37 (-50, -3) -> (-50, 3)
  line L38 (-50, 3) -> (-53, 3)
  line L39 (-53, 3) -> (-53, -3)
  line L40 (-68, -15) -> (-62, -15)
  line L41 (-62, -15) -> (-62, -12)
  line L42 (-62, -12) -> (-68, -12)
  line L43 (-68, -12) -> (-68, -15)
  line L44 (-68, 12) -> (-62, 12)
  line L45 (-62, 12) -> (-62, 15)
  line L46 (-62, 15) -> (-68, 15)
  line L47 (-68, 15) -> (-68, 12)
  line L48 (-80, 29.5) -> (-77, 29.5)
  line L49 (-77, 29.5) -> (-77, 35.5)
  line L50 (-77, 35.5) -> (-80, 35.5)
  line L51 (-80, 35.5) -> (-80, 29.5)
  line L52 (-53, 29.5) -> (-50, 29.5)
  line L53 (-50, 29.5) -> (-50, 35.5)
  line L54 (-50, 35.5) -> (-53, 35.5)
  line L55 (-53, 35.5) -> (-53, 29.5)
  line L56 (-68, 17.5) -> (-62, 17.5)
  line L57 (-62, 17.5) -> (-62, 20.5)
  line L58 (-62, 20.5) -> (-68, 20.5)
  line L59 (-68, 20.5) -> (-68, 17.5)
  line L60 (-68, 44.5) -> (-62, 44.5)
  line L61 (-62, 44.5) -> (-62, 47.5)
  line L62 (-62, 47.5) -> (-68, 47.5)
  line L63 (-68, 47.5) -> (-68, 44.5)
  line L64 (-80, 62) -> (-77, 62)
  line L65 (-77, 62) -> (-77, 68)
  line L66 (-77, 68) -> (-80, 68)
  line L67 (-80, 68) -> (-80, 62)
  line L68 (-53, 62) -> (-50, 62)
  line L69 (-50, 62) -> (-50, 68)
  line L70 (-50, 68) -> (-53, 68)
  line L71 (-53, 68) -> (-53, 62)
  line L72 (-68, 50) -> (-62, 50)
  line L73 (-62, 50) -> (-62, 53)
  line L74 (-62, 53) -> (-68, 53)
  line L75 (-68, 53) -> (-68, 50)
  line L76 (-68, 77) -> (-62, 77)
  line L77 (-62, 77) -> (-62, 80)
  line L78 (-62, 80) -> (-68, 80)
  line L79 (-68, 80) -> (-68, 77)
  line L80 (-47.5, -68) -> (-44.5, -68)
  line L81 (-44.5, -68) -> (-44.5, -62)
  line L82 (-44.5, -62) -> (-47.5, -62)
  line L83 (-47.5, -62) -> (-47.5, -68)
  line L84 (-20.5, -68) -> (-17.5, -68)
  line L85 (-17.5, -68) -> (-17.5, -62)
  line L86 (-17.5, -62) -> (-20.5, -62)
  line L87 (-20.5, -62) -> (-20.5, -68)
  line L88 (-35.5, -80) -> (-29.5, -80)
  line L89 (-29.5, -80) -> (-29.5, -77)
  line L90 (-29.5, -77) -> (-35.5, -77)
  line L91 (-35.5, -77) -> (-35.5, -80)
  line L92 (-35.5, -53) -> (-29.5, -53)
  line L93 (-29.5, -53) -> (-29.5, -50)
  line L94 (-29.5, -50) -> (-35.5, -50)
  line L95 (-35.5, -50) -> (-35.5, -53)
  line L96 (-47.5, -35.5) -> (-44.5, -35.5)
  line L97 (-44.5, -35.5) -> (-44.5, -29.5)
  line L98 (-44.5, -29.5) -> (-47.5, -29.5)
  line L99 (-47.5, -29.5) -> (-47.5, -35.5)
  line L100 (-20.5, -35.5) -> (-17.5, -35.5)
  line L101 (-17.5, -35.5) -> (-17.5, -29.5)
  line L102 (-17.5, -29.5) -> (-20.5, -29.5)
  line L103 (-20.5, -29.5) -> (-20.5, -35.5)
  line L104 (-35.5, -47.5) -> (-29.5, -47.5)
  line L105 (-29.5, -47.5) -> (-29.5, -44.5)
  line L106 (-29.5, -44.5) -> (-35.5, -44.5)
  line L107 (-35.5, -44.5) -> (-35.5, -47.5)
  line L108 (-35.5, -20.5) -> (-29.5, -20.5)
  line L109 (-29.5, -20.5) -> (-29.5, -17.5)
  line L110 (-29.5, -17.5) -> (-35.5, -17.5)
  line L111 (-35.5, -17.5) -> (-35.5, -20.5)
  line L112 (-47.5, -3) -> (-44.5, -3)
  line L113 (-44.5, -3) -> (-44.5, 3)
  line L114 (-44.5, 3) -> (-47.5, 3)
  line L115 (-47.5, 3) -> (-47.5, -3)
  line L116 (-20.5, -3) -> (-17.5, -3)
  line L117 (-17.5, -3) -> (-17.5, 3)
  line L118 (-17.5, 3) -> (-20.5, 3)
  line L119 (-20.5, 3) -> (-20.5, -3)
  line L120 (-35.5, -15) -> (-29.5, -15)
  line L121 (-29.5, -15) -> (-29.5, -12)
  line L122 (-29.5, -12) -> (-35.5, -12)
  line L123 (-35.5, -12) -> (-35.5, -15)
  line L124 (-35.5, 12) -> (-29.5, 12)
  line L125 (-29.5, 12) -> (-29.5, 15)
  line L126 (-29.5, 15) -> (-35.5, 15)
  line L127 (-35.5, 15) -> (-35.5, 12)
  line L128 (-47.5, 29.5) -> (-44.5, 29.5)
  line L129 (-44.5, 29.5) -> (-44.5, 35.5)
  line L130 (-44.5, 35.5) -> (-47.5, 35.5)
  line L131 (-47.5, 35.5) -> (-47.5, 29.5)
  line L132 (-20.5, 29.5) -> (-17.5, 29.5)
  line L133 (-17.5, 29.5) -> (-17.5, 35.5)
  line L134 (-17.5, 35.5) -> (-20.5, 35.5)
  line L135 (-20.5, 35.5) -> (-20.5, 29.5)
  line L136 (-35.5, 17.5) -> (-29.5, 17.5)
  line L137 (-29.5, 17.5) -> (-29.5, 20.5)
  line L138 (-29.5, 20.5) -> (-35.5, 20.5)
  line L139 (-35.5, 20.5) -> (-35.5, 17.5)
  line L140 (-35.5, 44.5) -> (-29.5, 44.5)
  line L141 (-29.5, 44.5) -> (-29.5, 47.5)
  line L142 (-29.5, 47.5) -> (-35.5, 47.5)
  line L143 (-35.5, 47.5) -> (-35.5, 44.5)
  line L144 (-47.5, 62) -> (-44.5, 62)
  line L145 (-44.5, 62) -> (-44.5, 68)
  line L146 (-44.5, 68) -> (-47.5, 68)
  line L147 (-47.5, 68) -> (-47.5, 62)
  line L148 (-20.5, 62) -> (-17.5, 62)
  line L149 (-17.5, 62) -> (-17.5, 68)
  line L150 (-17.5, 68) -> (-20.5, 68)
  line L151 (-20.5, 68) -> (-20.5, 62)
  line L152 (-35.5, 50) -> (-29.5, 50)
  line L153 (-29.5, 50) -> (-29.5, 53)
  line L154 (-29.5, 53) -> (-35.5, 53)
  line L155 (-35.5, 53) -> (-35.5, 50)
  line L156 (-35.5, 77) -> (-29.5, 77)
  line L157 (-29.5, 77) -> (-29.5, 80)
  line L158 (-29.5, 80) -> (-35.5, 80)
  line L159 (-35.5, 80) -> (-35.5, 77)
  line L160 (-15, -68) -> (-12, -68)
  line L161 (-12, -68) -> (-12, -62)
  line L162 (-12, -62) -> (-15, -62)
  line L163 (-15, -62) -> (-15, -68)
  line L164 (12, -68) -> (15, -68)
  line L165 (15, -68) -> (15, -62)
  line L166 (15, -62) -> (12, -62)
  line L167 (12, -62) -> (12, -68)
  line L168 (-3, -80) -> (3, -80)
  line L169 (3, -80) -> (3, -77)
  line L170 (3, -77) -> (-3, -77)
  line L171 (-3, -77) -> (-3, -80)
  line L172 (-3, -53) -> (3, -53)
  line L173 (3, -53) -> (3, -50)
  line L174 (3, -50) -> (-3, -50)
  line L175 (-3, -50) -> (-3, -53)
  line L176 (-15, -35.5) -> (-12, -35.5)
  line L177 (-12, -35.5) -> (-12, -29.5)
  line L178 (-12, -29.5) -> (-15, -29.5)
  line L179 (-15, -29.5) -> (-15, -35.5)
  line L180 (12, -35.5) -> (15, -35.5)
  line L181 (15, -35.5) -> (15, -29.5)
  line L182 (15, -29.5) -> (12, -29.5)
  line L183 (12, -29.5) -> (12, -35.5)
  line L184 (-3, -47.5) -> (3, -47.5)
  line L185 (3, -47.5) -> (3, -44.5)
  line L186 (3, -44.5) -> (-3, -44.5)
  line L187 (-3, -44.5) -> (-3, -47.5)
  line L188 (-3, -20.5) -> (3, -20.5)
  line L189 (3, -20.5) -> (3, -17.5)
  line L190 (3, -17.5) -> (-3, -17.5)
  line L191 (-3, -17.5) -> (-3, -20.5)
  line L192 (-15, -3) -> (-12, -3)
  line L193 (-12, -3) -> (-12, 3)
  line L194 (-12, 3) -> (-15, 3)
  line L195 (-15, 3) -> (-15, -3)
  line L196 (12, -3) -> (15, -3)
  line L197 (15, -3) -> (15, 3)
  line L198 (15, 3) -> (12, 3)
  line L199 (12, 3) -> (12, -3)
  line L200 (-3, -15) -> (3, -15)
  line L201 (3, -15) -> (3, -12)
  line L202 (3, -12) -> (-3, -12)
  line L203 (-3, -12) -> (-3, -15)
  line L204 (-3, 12) -> (3, 12)
  line L205 (3, 12) -> (3, 15)
  line L206 (3, 15) -> (-3, 15)
  line L207 (-3, 15) -> (-3, 12)
  line L208 (-15, 29.5) -> (-12, 29.5)
  line L209 (-12, 29.5) -> (-12, 35.5)
  line L210 (-12, 35.5) -> (-15, 35.5)
  line L211 (-15, 35.5) -> (-15, 29.5)
  line L212 (12, 29.5) -> (15, 29.5)
  line L213 (15, 29.5) -> (15, 35.5)
  line L214 (15, 35.5) -> (12, 35.5)
  line L215 (12, 35.5) -> (12, 29.5)
  line L216 (-3, 17.5) -> (3, 17.5)
  line L217 (3, 17.5) -> (3, 20.5)
  line L218 (3, 20.5) -> (-3, 20.5)
  line L219 (-3, 20.5) -> (-3, 17.5)
  line L220 (-3, 44.5) -> (3, 44.5)
  line L221 (3, 44.5) -> (3, 47.5)
  line L222 (3, 47.5) -> (-3, 47.5)
  line L223 (-3, 47.5) -> (-3, 44.5)
  line L224 (-15, 62) -> (-12, 62)
  line L225 (-12, 62) -> (-12, 68)
  line L226 (-12, 68) -> (-15, 68)
  line L227 (-15, 68) -> (-15, 62)
  line L228 (12, 62) -> (15, 62)
  line L229 (15, 62) -> (15, 68)
  line L230 (15, 68) -> (12, 68)
  line L231 (12, 68) -> (12, 62)
  line L232 (-3, 50) -> (3, 50)
  line L233 (3, 50) -> (3, 53)
  line L234 (3, 53) -> (-3, 53)
  line L235 (-3, 53) -> (-3, 50)
  line L236 (-3, 77) -> (3, 77)
  line L237 (3, 77) -> (3, 80)
  line L238 (3, 80) -> (-3, 80)
  line L239 (-3, 80) -> (-3, 77)
  line L240 (17.5, -68) -> (20.5, -68)
  line L241 (20.5, -68) -> (20.5, -62)
  line L242 (20.5, -62) -> (17.5, -62)
  line L243 (17.5, -62) -> (17.5, -68)
  line L244 (44.5, -68) -> (47.5, -68)
  line L245 (47.5, -68) -> (47.5, -62)
  line L246 (47.5, -62) -> (44.5, -62)
  line L247 (44.5, -62) -> (44.5, -68)
  line L248 (29.5, -80) -> (35.5, -80)
  line L249 (35.5, -80) -> (35.5, -77)
  line L250 (35.5, -77) -> (29.5, -77)
  line L251 (29.5, -77) -> (29.5, -80)
  line L252 (29.5, -53) -> (35.5, -53)
  line L253 (35.5, -53) -> (35.5, -50)
  line L254 (35.5, -50) -> (29.5, -50)
  line L255 (29.5, -50) -> (29.5, -53)
  line L256 (17.5, -35.5) -> (20.5, -35.5)
  line L257 (20.5, -35.5) -> (20.5, -29.5)
  line L258 (20.5, -29.5) -> (17.5, -29.5)
  line L259 (17.5, -29.5) -> (17.5, -35.5)
  line L260 (44.5, -35.5) -> (47.5, -35.5)
  line L261 (47.5, -35.5) -> (47.5, -29.5)
  line L262 (47.5, -29.5) -> (44.5, -29.5)
  line L263 (44.5, -29.5) -> (44.5, -35.5)
  line L264 (29.5, -47.5) -> (35.5, -47.5)
  line L265 (35.5, -47.5) -> (35.5, -44.5)
  line L266 (35.5, -44.5) -> (29.5, -44.5)
  line L267 (29.5, -44.5) -> (29.5, -47.5)
  line L268 (29.5, -20.5) -> (35.5, -20.5)
  line L269 (35.5, -20.5) -> (35.5, -17.5)
  line L270 (35.5, -17.5) -> (29.5, -17.5)
  line L271 (29.5, -17.5) -> (29.5, -20.5)
  line L272 (17.5, -3) -> (20.5, -3)
  line L273 (20.5, -3) -> (20.5, 3)
  line L274 (20.5, 3) -> (17.5, 3)
  line L275 (17.5, 3) -> (17.5, -3)
  line L276 (44.5, -3) -> (47.5, -3)
  line L277 (47.5, -3) -> (47.5, 3)
  line L278 (47.5, 3) -> (44.5, 3)
  line L279 (44.5, 3) -> (44.5, -3)
  line L280 (29.5, -15) -> (35.5, -15)
  line L281 (35.5, -15) -> (35.5, -12)
  line L282 (35.5, -12) -> (29.5, -12)
  line L283 (29.5, -12) -> (29.5, -15)
  line L284 (29.5, 12) -> (35.5, 12)
  line L285 (35.5, 12) -> (35.5, 15)
  line L286 (35.5, 15) -> (29.5, 15)
  line L287 (29.5, 15) -> (29.5, 12)
  line L288 (17.5, 29.5) -> (20.5, 29.5)
  line L289 (20.5, 29.5) -> (20.5, 35.5)
  line L290 (20.5, 35.5) -> (17.5, 35.5)
  line L291 (17.5, 35.5) -> (17.5, 29.5)
  line L292 (44.5, 29.5) -> (47.5, 29.5)
  line L293 (47.5, 29.5) -> (47.5, 35.5)
  line L294 (47.5, 35.5) -> (44.5, 35.5)
  line L295 (44.5, 35.5) -> (44.5, 29.5)
  line L296 (29.5, 17.5) -> (35.5, 17.5)
  line L297 (35.5, 17.5) -> (35.5, 20.5)
  line L298 (35.5, 20.5) -> (29.5, 20.5)
  line L299 (29.5, 20.5) -> (29.5, 17.5)
  line L300 (29.5, 44.5) -> (35.5, 44.5)
  line L301 (35.5, 44.5) -> (35.5, 47.5)
  line L302 (35.5, 47.5) -> (29.5, 47.5)
  line L303 (29.5, 47.5) -> (29.5, 44.5)
  line L304 (17.5, 62) -> (20.5, 62)
  line L305 (20.5, 62) -> (20.5, 68)
  line L306 (20.5, 68) -> (17.5, 68)
  line L307 (17.5, 68) -> (17.5, 62)
  line L308 (44.5, 62) -> (47.5, 62)
  line L309 (47.5, 62) -> (47.5, 68)
  line L310 (47.5, 68) -> (44.5, 68)
  line L311 (44.5, 68) -> (44.5, 62)
  line L312 (29.5, 50) -> (35.5, 50)
  line L313 (35.5, 50) -> (35.5, 53)
  line L314 (35.5, 53) -> (29.5, 53)
  line L315 (29.5, 53) -> (29.5, 50)
  line L316 (29.5, 77) -> (35.5, 77)
  line L317 (35.5, 77) -> (35.5, 80)
  line L318 (35.5, 80) -> (29.5, 80)
  line L319 (29.5, 80) -> (29.5, 77)
  line L320 (50, -68) -> (53, -68)
  line L321 (53, -68) -> (53, -62)
  line L322 (53, -62) -> (50, -62)
  line L323 (50, -62) -> (50, -68)
  line L324 (77, -68) -> (80, -68)
  line L325 (80, -68) -> (80, -62)
  line L326 (80, -62) -> (77, -62)
  line L327 (77, -62) -> (77, -68)
  line L328 (62, -80) -> (68, -80)
  line L329 (68, -80) -> (68, -77)
  line L330 (68, -77) -> (62, -77)
  line L331 (62, -77) -> (62, -80)
  line L332 (62, -53) -> (68, -53)
  line L333 (68, -53) -> (68, -50)
  line L334 (68, -50) -> (62, -50)
  line L335 (62, -50) -> (62, -53)
  line L336 (50, -35.5) -> (53, -35.5)
  line L337 (53, -35.5) -> (53, -29.5)
  line L338 (53, -29.5) -> (50, -29.5)
  line L339 (50, -29.5) -> (50, -35.5)
  line L340 (77, -35.5) -> (80, -35.5)
  line L341 (80, -35.5) -> (80, -29.5)
  line L342 (80, -29.5) -> (77, -29.5)
  line L343 (77, -29.5) -> (77, -35.5)
  line L344 (62, -47.5) -> (68, -47.5)
  line L345 (68, -47.5) -> (68, -44.5)
  line L346 (68, -44.5) -> (62, -44.5)
  line L347 (62, -44.5) -> (62, -47.5)
  line L348 (62, -20.5) -> (68, -20.5)
  line L349 (68, -20.5) -> (68, -17.5)
  line L350 (68, -17.5) -> (62, -17.5)
  line L351 (62, -17.5) -> (62, -20.5)
  line L352 (50, -3) -> (53, -3)
  line L353 (53, -3) -> (53, 3)
  line L354 (53, 3) -> (50, 3)
  line L355 (50, 3) -> (50, -3)
  line L356 (77, -3) -> (80, -3)
  line L357 (80, -3) -> (80, 3)
  line L358 (80, 3) -> (77, 3)
  line L359 (77, 3) -> (77, -3)
  line L360 (62, -15) -> (68, -15)
  line L361 (68, -15) -> (68, -12)
  line L362 (68, -12) -> (62, -12)
  line L363 (62, -12) -> (62, -15)
  line L364 (62, 12) -> (68, 12)
  line L365 (68, 12) -> (68, 15)
  line L366 (68, 15) -> (62, 15)
  line L367 (62, 15) -> (62, 12)
  line L368 (50, 29.5) -> (53, 29.5)
  line L369 (53, 29.5) -> (53, 35.5)
  line L370 (53, 35.5) -> (50, 35.5)
  line L371 (50, 35.5) -> (50, 29.5)
  line L372 (77, 29.5) -> (80, 29.5)
  line L373 (80, 29.5) -> (80, 35.5)
  line L374 (80, 35.5) -> (77, 35.5)
  line L375 (77, 35.5) -> (77, 29.5)
  line L376 (62, 17.5) -> (68, 17.5)
  line L377 (68, 17.5) -> (68, 20.5)
  line L378 (68, 20.5) -> (62, 20.5)
  line L379 (62, 20.5) -> (62, 17.5)
  line L380 (62, 44.5) -> (68, 44.5)
  line L381 (68, 44.5) -> (68, 47.5)
  line L382 (68, 47.5) -> (62, 47.5)
  line L383 (62, 47.5) -> (62, 44.5)
  line L384 (50, 62) -> (53, 62)
  line L385 (53, 62) -> (53, 68)
  line L386 (53, 68) -> (50, 68)
  line L387 (50, 68) -> (50, 62)
  line L388 (77, 62) -> (80, 62)
  line L389 (80, 62) -> (80, 68)
  line L390 (80, 68) -> (77, 68)
  line L391 (77, 68) -> (77, 62)
  line L392 (62, 50) -> (68, 50)
  line L393 (68, 50) -> (68, 53)
  line L394 (68, 53) -> (62, 53)
  line L395 (62, 53) -> (62, 50)
  line L396 (62, 77) -> (68, 77)
  line L397 (68, 77) -> (68, 80)
  line L398 (68, 80) -> (62, 80)
  line L399 (62, 80) -> (62, 77)
extrude "spacer_pads (1)" add sketch "spacer_pads" along normal blind 0.6 in component "drop_plate"
ref_plane "WorkPlane6" through (0, 0, 7.25) normal (0, 0, 1) x (1, 0, 0) in component "drop_plate"